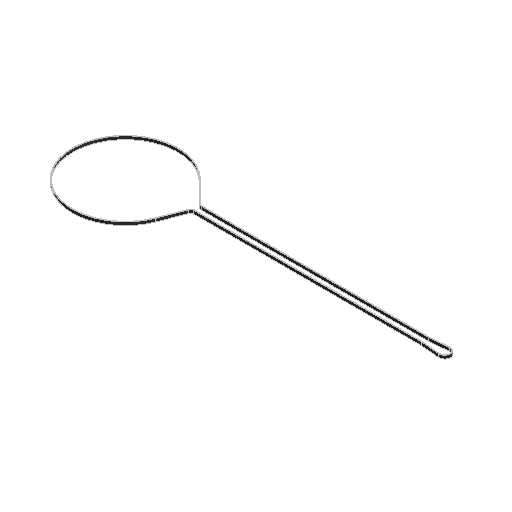
# Autodesk Inventor part: COTS_GENERIC_HTD3M_6mm_1530mm_Closed_belt_B_Axis
Saved by Autodesk Inventor 2027 (Build 310192060, 192F)
## iProperties
Created: 2026-01-17
Part Number: COTS_GENERIC_HTD3M_6mm_1530mm_Closed_belt_B_Axis
Material: Generic
Document SubType Name: Modeling
Designer: User
Density: 1 g/cm^3
Appearance: Rubber - Black
Author: User
Autodesk Inventor part; units mm, degrees
ref_plane "YZ Plane" through (0, 0, 0) normal (1, 0, 0) x (0, 1, 0)
ref_plane "XZ Plane" through (0, 0, 0) normal (0, 1, 0) x (-1, 0, 0)
ref_plane "XY Plane" through (0, 0, 0) normal (0, 0, 1) x (1, 0, 0)
sketch "Sketch1" plane through (0, 0, 0) normal (0, 1, 0) x (-1, 0, 0)
  arc A0 (-9.1691, 9.1273) -> (-9.1691, -9.1273) centre (-10, 0) ccw
  arc A1 (24.8654, 6.0288) -> (25.5, 6) centre (25.5, 13) ccw
  arc A2 (25.5, -6) -> (24.8654, -6.0288) centre (25.5, -13) ccw
  arc A3 (483.3271, -47.8329) -> (461.7969, 53.8173) centre (550.5, 19.5) ccw
  line L0 (43.5, -25.5) -> (43.5, 64.5)
  line L1 (426.5, 64.5) -> (426.5, -25.5)
  arc A4 (438.5, 6) -> (445.0285, 10.4743) centre (438.5, 13) ccw
  arc A5 (443.4439, -8.0444) -> (438.5, -6) centre (438.5, -13) ccw
  line L2 (461.7969, 53.8173) -> (445.0285, 10.4743)
  line L3 (443.4439, -8.0444) -> (483.3271, -47.8329)
  line L4 (25.5, -6) -> (438.5, -6)
  line L5 (24.8654, 6.0288) -> (-9.1691, 9.1273)
  line L6 (-9.1691, -9.1273) -> (24.8654, -6.0288)
  line L7 (438.5, 6) -> (25.5, 6)
  line L8 (-9.0603, 10.3223) -> (24.9742, 7.2239)
  arc A6 (24.9742, 7.2239) -> (25.5, 7.2) centre (25.5, 13) ccw
  line L9 (25.5, 7.2) -> (438.5, 7.2)
  arc A7 (438.5, 7.2) -> (443.9093, 10.9073) centre (438.5, 13) ccw
  line L10 (443.9093, 10.9073) -> (460.6778, 54.2503)
  arc A8 (482.4796, -48.6824) -> (460.6778, 54.2503) centre (550.5, 19.5) ccw
  line L11 (482.4796, -48.6824) -> (442.5963, -8.8939)
  arc A9 (442.5963, -8.8939) -> (438.5, -7.2) centre (438.5, -13) ccw
  line L12 (438.5, -7.2) -> (25.5, -7.2)
  arc A10 (25.5, -7.2) -> (24.9742, -7.2239) centre (25.5, -13) ccw
  line L13 (24.9742, -7.2239) -> (-9.0603, -10.3223)
  arc A11 (-9.0603, 10.3223) -> (-9.0603, -10.3223) centre (-10, 0) ccw
  point P0 (0, 0)
  dimension "d0" = 18.33
  dimension "d1" = 14
  dimension "d2" = 14
  dimension "d3" = 13
  dimension "d4" = 13
  dimension "d5" = 35.5
  dimension "d6" = 10
  dimension "d7" = 35.5
  dimension "d8" = 190.22
  dimension "d9" = 19.5
  dimension "d10" = 90
  dimension "d11" = 18
  dimension "d12" = 90
  dimension "d13" = 383
  dimension "d14" = 25.5
  dimension "d15" = 14
  dimension "d16" = 14
  dimension "d17" = 13
  dimension "d18" = 13
  dimension "d19" = 12
  dimension "d20" = 124
  dimension "d21" = 1.2
  constraints: 28 end point, 24 point on circle, 12 centre point, 12 tangent, 2 horizontal alignment, 2 vertical, 1 vertical alignment, 11 other
  measures "d0" diameter of A0
  measures "d1" diameter of A1
  measures "d2" diameter of A2
  measures "d3" vertical distance of A0.centre A1.centre
  measures "d4" vertical distance of A0.centre A2.centre
  measures "d5" horizontal distance of A0.centre A2.centre
  measures "d6" distance of A0.centre point (0, 0)
  measures "d7" horizontal distance of A0.centre A1.centre
  measures "d8" diameter of A3
  measures "d9" vertical distance of A3.centre point (0, 0)
  measures "d10" distance of L0.start L0.end
  measures "d11" distance from line of L0 A2.centre
  measures "d12" distance of L1.start L1.end
  measures "d13" distance between parallel lines of L0 L1
  measures "d14" vertical distance of L0.start point (0, 0)
  measures "d15" diameter of A4
  measures "d16" diameter of A5
  measures "d17" vertical distance of point (0, 0) A4.centre
  measures "d18" vertical distance of point (0, 0) A5.centre
  measures "d19" distance from line of L1 A5.centre
  measures "d20" distance from line of A3.centre L1
  measures "d21" distance between parallel lines of L5 L8
extrude "Extrusion1" add sketch "Sketch1" along normal blind 6 contours A0 L6 A2 L4 L0 L12 A10 L13 A11 L8 A6 L9 L7 A1 L5 | L0 L9 L1 L7 | L4 L1 L12 L0 | L1 L9 A7 L10 A8 L11 A9 L12 L4 A5 L3 A3 L2 A4 L7
equation "\"d4\" = d3"
equation "\"d7\" = d5"
equation "\"d18\" = d17"
body "Solid1"
